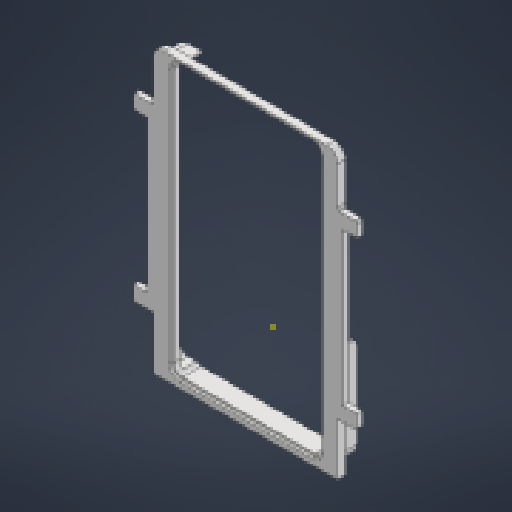
# Autodesk Inventor part: 屏幕安装
Saved by Autodesk Inventor 2025 (Build 290162000, 162)
## iProperties
Created: 2025-10-11
Part Number: 屏幕安装
Material: 常规
Document SubType Name: Modeling
Designer: HZD
Density: 1 g/cm^3
Appearance: 默认
Author: HZD
Autodesk Inventor part; units mm, degrees
ref_plane "YZ Plane" through (0, 0, 0) normal (1, 0, 0) x (0, 1, 0)
ref_plane "XZ Plane" through (0, 0, 0) normal (0, 1, 0) x (-1, 0, 0)
sketch "草图1" plane through (0, 0, 0) normal (0, 0, 1) x (1, 0, 0)
  line L0 (26.529804, -28.054816) -> (26.529804, -15.395352)
  arc A0 (23.655432, -31.89317) -> (26.529804, -28.054816) centre (22.529804, -28.054816) ccw
  line L1 (22.529804, -32.054816) -> (-37.232966, -32.054816)
  arc A1 (-41.232966, -28.054816) -> (-38.358594, -31.89317) centre (-37.232966, -28.054816) ccw
  line L2 (-41.232966, -28.054816) -> (-41.232966, -15.395352)
  arc A2 (-41.232966, -28.054816) -> (-37.232966, -32.054816) centre (-37.232966, -28.054816) ccw
  arc A3 (26.529804, 66.462032) -> (22.529804, 70.462032) centre (22.529804, 66.462032) ccw
  line L3 (-37.232966, 70.462032) -> (22.529804, 70.462032)
  arc A4 (-37.232966, 70.462032) -> (-41.232966, 66.462032) centre (-37.232966, 66.462032) ccw
  line L4 (-41.232966, 52.604648) -> (-41.232966, 66.462032)
  line L5 (-41.732966, 52.104648) -> (-40.232966, 52.104648)
  line L6 (-40.232966, 65.462032) -> (-40.232966, 52.104648)
  arc A5 (-36.232966, 69.462032) -> (-40.232966, 65.462032) centre (-36.232966, 65.462032) ccw
  line L7 (21.529804, 69.462032) -> (-36.232966, 69.462032)
  arc A6 (25.529804, 65.462032) -> (21.529804, 69.462032) centre (21.529804, 65.462032) ccw
  line L8 (25.529804, 52.104648) -> (25.529804, 65.462032)
  line L9 (25.529804, 52.104648) -> (27.029804, 52.104648)
  line L10 (26.529804, 66.462032) -> (26.529804, 52.604648)
  spline S0 degree 3 poles (23.655432, -31.89317) (23.288852, -32.000672) (22.904809, -32.054816) (22.529804, -32.054816) knots 0 0 0 0 1 1 1 1 construction
  spline S1 degree 3 poles (23.655432, -31.89317) (23.288852, -32.000672) (22.904809, -32.054816) (22.529804, -32.054816) knots 0 0 0 0 1 1 1 1
  line L11 (26.529804, -15.395352) -> (26.529804, 52.104648)
  line L12 (-41.232966, -15.395352) -> (-41.232966, 52.604648)
  arc A7 (-41.732966, 52.104648) -> (-41.232966, 52.604648) centre (-41.732966, 52.604648) ccw
  arc A8 (26.529804, 52.604648) -> (27.029804, 52.104648) centre (27.029804, 52.604648) ccw
  point P0 (-41.232966, 52.104648)
  constraints: 4 end point, 1 collinear, 1 parallel
extrude "拉伸1" add sketch "草图1" along normal blind 3 contours A0 S1 L1 A2 A1 L2 L12 L5 L6 A5 L7 A6 L8 L9 L11 L0 | L9 L8 A6 L7 A5 L6 L5 L12 L4 A4 L3 A3 L10 A8
sketch "草图2" plane through (0, 0, 3) normal (0, 0, 1) x (1, 0, 0)
  line L0 (-34.346505, 65.751209) -> (-34.346505, -27.728791)
  arc A0 (-34.346505, -27.728791) -> (-31.346505, -30.728791) centre (-31.346505, -27.728791) ccw
  line L1 (-31.346505, -30.728791) -> (17.253495, -30.728791)
  arc A1 (17.253495, -30.728791) -> (20.253495, -27.728791) centre (17.253495, -27.728791) ccw
  line L2 (20.253495, -27.728791) -> (20.253495, 65.751209)
  arc A2 (20.253495, 65.751209) -> (17.253495, 68.751209) centre (17.253495, 65.751209) ccw
  line L3 (17.253495, 68.751209) -> (-31.346505, 68.751209)
  arc A3 (-31.346505, 68.751209) -> (-34.346505, 65.751209) centre (-31.346505, 65.751209) ccw
  point P0 (0, 0)
extrude "拉伸2" cut sketch "草图2" against normal blind 7.5
sketch "草图3" plane through (0, 0, 3) normal (0, 0, 1) x (1, 0, 0)
  line L0 (-34.346505, 65.751209) -> (-34.346505, -27.728791)
  arc A0 (-34.346505, -27.728791) -> (-31.346505, -30.728791) centre (-31.346505, -27.728791) ccw
  line L1 (-31.346505, -30.728791) -> (17.253495, -30.728791)
  arc A1 (17.253495, -30.728791) -> (20.253495, -27.728791) centre (17.253495, -27.728791) ccw
  line L2 (20.253495, -27.728791) -> (20.253495, 65.751209)
  arc A2 (20.253495, 65.751209) -> (17.253495, 68.751209) centre (17.253495, 65.751209) ccw
  line L3 (17.253495, 68.751209) -> (-31.346505, 68.751209)
  arc A3 (-31.346505, 68.751209) -> (-34.346505, 65.751209) centre (-31.346505, 65.751209) ccw
  line L4 (-31.346505, 69.651209) -> (17.253495, 69.651209)
  arc A4 (21.153495, 65.751209) -> (17.253495, 69.651209) centre (17.253495, 65.751209) ccw
  line L5 (21.153495, 65.751209) -> (21.153495, -27.728791)
  arc A5 (17.253495, -31.628791) -> (21.153495, -27.728791) centre (17.253495, -27.728791) ccw
  line L6 (17.253495, -31.628791) -> (-31.346505, -31.628791)
  arc A6 (-35.246505, -27.728791) -> (-31.346505, -31.628791) centre (-31.346505, -27.728791) ccw
  line L7 (-35.246505, -27.728791) -> (-35.246505, 65.751209)
  arc A7 (-31.346505, 69.651209) -> (-35.246505, 65.751209) centre (-31.346505, 65.751209) ccw
  point P0 (0, 0)
  dimension "d5" = 0.9
  constraints: 8 end point, 8 point on circle, 4 centre point, 7 other
  measures "d5" distance between parallel lines of L3 L4
extrude "拉伸3" cut sketch "草图3" against normal blind 1
sketch "草图4" plane through (0, 0, 0) normal (0, 0, -1) x (-1, 0, 0)
  point P0 (0, 0)
sketch "草图7" plane through (0, 0, 0) normal (0, 0, -1) x (-1, 0, 0)
  line L0 (40.232966, 65.462032) -> (40.232966, -27.054816)
  arc A0 (36.232966, -31.054816) -> (40.232966, -27.054816) centre (36.232966, -27.054816) ccw
  line L1 (36.232966, -31.054816) -> (-21.529804, -31.054816)
  arc A1 (-25.529804, -27.054816) -> (-21.529804, -31.054816) centre (-21.529804, -27.054816) ccw
  line L2 (-25.529804, -27.054816) -> (-25.529804, 6.569991)
  line L3 (-25.529804, 30.569991) -> (-25.529804, 65.462032)
  arc A2 (-21.529804, 69.462032) -> (-25.529804, 65.462032) centre (-21.529804, 65.462032) ccw
  line L4 (-21.529804, 69.462032) -> (-0.332709, 69.462032)
  line L5 (0.88364, 67.17843) -> (30.38364, 67.17843)
  line L6 (31.167291, 69.462032) -> (36.232966, 69.462032)
  arc A3 (40.232966, 65.462032) -> (36.232966, 69.462032) centre (36.232966, 65.462032) ccw
  line L7 (31.167291, 68.462032) -> (36.232966, 68.462032)
  arc A4 (39.232966, 65.462032) -> (36.232966, 68.462032) centre (36.232966, 65.462032) ccw
  line L8 (39.232966, 65.462032) -> (39.232966, -27.054816)
  arc A5 (36.232966, -30.054816) -> (39.232966, -27.054816) centre (36.232966, -27.054816) ccw
  line L9 (36.232966, -30.054816) -> (-21.529804, -30.054816)
  arc A6 (-24.529804, -27.054816) -> (-21.529804, -30.054816) centre (-21.529804, -27.054816) ccw
  line L10 (-24.529804, -27.054816) -> (-24.529804, 6.569991)
  line L11 (31.167291, 68.462032) -> (31.167291, 69.462032)
  line L12 (-24.529804, 6.569991) -> (-25.529804, 6.569991)
  point P0 (0, 0)
  dimension "d15" = 1
  constraints: 12 end point, 6 point on circle, 3 centre point, 1 horizontal, 1 vertical, 6 other
  measures "d15" radial gap between concentric circles of A0 A5
extrude "拉伸6" add sketch "草图7" along normal blind 5
sketch "草图8" plane through (0, 0, 0) normal (0, 0, 1) x (1, 0, 0)
  line L0 (-34.346505, 65.751209) -> (-34.346505, -27.728791)
  arc A0 (-34.346505, -27.728791) -> (-31.346505, -30.728791) centre (-31.346505, -27.728791) ccw
  line L1 (-31.346505, -30.728791) -> (17.253495, -30.728791)
  arc A1 (17.253495, -30.728791) -> (20.253495, -27.728791) centre (17.253495, -27.728791) ccw
  line L2 (20.253495, -27.728791) -> (20.253495, 65.751209)
  arc A2 (20.253495, 65.751209) -> (17.253495, 68.751209) centre (17.253495, 65.751209) ccw
  line L3 (17.253495, 68.751209) -> (-31.346505, 68.751209)
  arc A3 (-31.346505, 68.751209) -> (-34.346505, 65.751209) centre (-31.346505, 65.751209) ccw
  point P0 (0, 0)
extrude "拉伸7" cut sketch "草图8" against normal blind 9.25
sketch "草图9" plane through (0, 0, 3) normal (0, 0, 1) x (1, 0, 0)
  line L0 (27.029804, 52.104648) -> (32.648419, 52.104648)
  line L1 (33.148419, 52.104648) -> (32.648419, 52.104648)
  spline S0 degree 3 poles (34.148419, 51.104648) (34.148419, 51.170489) (34.141835, 51.236705) (34.115996, 51.365665) (34.096737, 51.428417) (34.022824, 51.606598) (33.951182, 51.712154) (33.784629, 51.88618) (33.674627, 51.965844) (33.425117, 52.075211) (33.285321, 52.104648) (33.148419, 52.104648) knots 0 0 0 0 0.12055566 0.12055566 0.24111131 0.24111131 0.48222262 0.48222262 0.74111131 0.74111131 1 1 1 1
  line L2 (34.148419, 51.104648) -> (34.148419, 46.104648)
  line L3 (34.148419, 46.104648) -> (26.529804, 46.104648)
  line L4 (26.529804, -28.054816) -> (26.529804, 66.462032)
  line L5 (26.529804, 51.704648) -> (32.648419, 51.704648)
  line L6 (32.648419, 51.704648) -> (33.148419, 51.704648)
  line L7 (33.748419, 51.104648) -> (33.748419, 46.504648)
  line L8 (33.748419, 46.504648) -> (26.529804, 46.504648)
  line L9 (26.395644, 18.630876) -> (29.454952, 18.630876)
  line L10 (27.029804, -14.842896) -> (32.648419, -14.842896)
  line L11 (33.148419, -14.842896) -> (32.648419, -14.842896)
  spline S1 degree 4 poles (34.148419, -13.842896) (34.147464, -13.970207) (34.120263, -14.145689) (34.024848, -14.35767) (33.858506, -14.557591) (33.654281, -14.724861) (33.446838, -14.814972) (33.271546, -14.842036) (33.148419, -14.842896) knots 0 0 0 0 0 0.31579678 0.43970695 0.5630279 0.68661274 1 1 1 1 1
  line L12 (34.148419, -13.842896) -> (34.148419, -8.842896)
  line L13 (34.148419, -8.842896) -> (26.529804, -8.842896)
  line L14 (26.529804, -14.442896) -> (32.648419, -14.442896)
  line L15 (32.648419, -14.442896) -> (33.148419, -14.442896)
  line L16 (33.748419, -13.842896) -> (33.748419, -9.242896)
  line L17 (33.748419, -9.242896) -> (26.529804, -9.242896)
  line L18 (29.371515, 45.084716) -> (32.559483, 45.084977)
  line L19 (28.514172, 46.504648) -> (26.529804, 46.504648)
  line L20 (26.529804, 46.504648) -> (26.529804, -9.242896)
  line L21 (26.529804, -9.242896) -> (28.514172, -9.242896)
  line L22 (28.514172, -9.242896) -> (28.514172, 46.504648)
  arc A0 (33.148419, -14.442896) -> (33.748419, -13.842896) centre (33.148419, -13.842896) ccw
  spline S2 degree 5 poles (33.148419, 51.704648) (33.33677, 51.703957) (33.525786, 51.631555) (33.6743, 51.481162) (33.748471, 51.293262) (33.748419, 51.104648) knots 0 0 0 0 0 0 1 1 1 1 1 1
  point P0 (0, 0)
  point P1 (34.127458, -14.04657)
  point P2 (34.066592, -14.239068)
  point P3 (33.971626, -14.410325)
  point P4 (33.852866, -14.552635)
  point P5 (33.707952, -14.671478)
  point P6 (33.537064, -14.764279)
  point P7 (33.346704, -14.822785)
  dimension "d20" = 0.4
  constraints: 36 end point, 12 symmetric about line, 4 parallel, 3 horizontal, 2 point on circle, 1 centre point, 1 perpendicular, 1 point on line, 1 tangent, 16 other
  measures "d20" distance between parallel lines of L2 L7
extrude "拉伸8" add sketch "草图9" against normal blind 2
fillet "圆角1" radius 1 1 edges at (26.5298, 51.7046, 2)
ref_plane "工作平面1" through (-7.351581, -28.054816, 0) normal (1, 0, 0) x (0, 0, -1)
mirror "镜像1" about plane through (-7.351581, -28.054816, 0) normal (1, 0, 0) of "拉伸8"
sketch "草图10" plane through (-39.232966, -27.054816, 0) normal (1, 0, 0) x (0, 0, -1)
  line L0 (5, 92.516848) -> (5, 0)
  line L1 (0, -0.673975) -> (0, 92.806025)
  line L2 (5, 54.181025) -> (0, 54.181025)
  line L3 (0, 54.181025) -> (0, 33.417754)
  line L4 (0, 33.417754) -> (5, 33.417754)
  line L5 (5, 33.417754) -> (5, 54.181025)
  point P0 (0, 27.054816)
  constraints: 8 end point, 2 parallel, 2 point on line, 1 horizontal, 1 perpendicular
extrude "拉伸9" cut sketch "草图10" against normal blind 3
fillet "圆角3" radius 2 3 edges at (-39.733, 27.1262, -5) (-39.733, 6.3629, -5) (25.0298, 6.57, -5)
delete faces "删除1" heal yes whole lump no faces at (-38.411987, -31.877107, 2) (25.552308, -30.674828, 2) (22.780855, -32.046803, 1.333333)
move faces "移动1" translate (0, -1.75, 0) faces at (-18.645376, -32.054816, 2)
fillet "圆角4" radius 2 1 edges at (-7.3516, -33.8048, 3)
